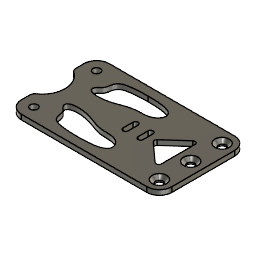
assembly frame (Autodesk Fusion 360 archive; units mm, degrees)
design "top plate"
part number: 2026-08-28-11-28-22-394
Autodesk Fusion 360 part; units mm, degrees
sketch "Sketch1" plane through (0, 0, 0) normal (0, 0, 1) x (1, 0, 0)
  line L0 (-30, 17.5) -> (30, 17.5)
  line L1 (30, 17.5) -> (30, -17.5)
  line L2 (30, -17.5) -> (-30, -17.5)
  line L3 (-30, -17.5) -> (-30, 17.5)
  dimension "d1" = 60
  dimension "d2" = 35
  dimension "d3" = 30
  dimension "d4" = 17.5
  constraint horizontal L0
  constraint vertical L1
  constraint horizontal L2
  constraint vertical L3
  measures "d1" distance of L1.end L2.end
  measures "d2" distance of L0 L2
  measures "d3" horizontal distance of origin L2.end
  measures "d4" vertical distance of origin L2.end
extrude "Extrude1" add sketch "Sketch1" along normal blind 2 contours L0 L1 L2 L3 picked at (-10, 5.833333)
sketch "Sketch2" plane through (0, 0, 2) normal (0, 0, 1) x (-1, 0, 0)
  line L0 (30, 17.5) -> (-30, 17.5)
  line L1 (-30, 17.5) -> (-30, -17.5)
  line L2 (-30, -17.5) -> (30, -17.5)
  line L3 (30, -17.5) -> (30, 17.5)
  point P0 (-25, -12.5)
  point P1 (-25, 0)
  point P2 (-25, 12.5)
  dimension "d7" = 25
  dimension "d8" = 12.5
  dimension "d9" = 5
  constraint vertical P0 P2
  constraint vertical P1 P2
  constraint horizontal origin P1
  measures "d7" distance of P0 P2
  measures "d8" distance of P1 P2
  measures "d9" distance of L1 P1
hole "Hole1" at (25, 12.5, 2) at (25, 0, 2) at (25, -12.5, 2) direction (0, 0, -1) diameter 3 end through all countersink diameter 5.76 countersink angle 90
sketch "Sketch3" plane through (0, 0, 2) normal (0, 0, 1) x (-1, 0, 0)
  circle A0 centre (-25, 0) radius 2.88
  circle A1 centre (-25, -12.5) radius 2.88
  circle A2 centre (-25, 12.5) radius 2.88
  line L0 (30, 17.5) -> (-30, 17.5)
  line L1 (-30, 17.5) -> (-30, -17.5)
  line L2 (-30, -17.5) -> (30, -17.5)
  line L3 (30, -17.5) -> (30, 17.5)
  point P0 (25, -12.5)
  point P1 (25, 12.5)
  dimension "d14" = 5
  constraint vertical P0 P1
  constraint horizontal A2.centre P1
  constraint horizontal A1.centre P0
  measures "d14" distance of L3 P0
hole "Hole2" at (-25, 12.5, 2) at (-25, -12.5, 2) direction (0, 0, -1) diameter 3 end through all
fillet "Fillet1" radius 5 4 edges at (-30, -17.5, 1) (-30, 17.5, 1) (30, -17.5, 1) (30, 17.5, 1)
sketch "Sketch4" plane through (0, 0, 2) normal (0, 0, 1) x (-1, 0, 0)
  circle A0 centre (25, -12.5) radius 1.5
  circle A1 centre (25, 12.5) radius 1.5
  circle A2 centre (-25, 0) radius 2.88
  circle A3 centre (-25, -12.5) radius 2.88
  circle A4 centre (-25, 12.5) radius 2.88
  arc A5 (-30, -12.5) -> (-25, -17.5) centre (-25, -12.5) ccw
  line L0 (-25, -17.5) -> (25, -17.5)
  arc A6 (25, -17.5) -> (30, -12.5) centre (25, -12.5) ccw
  line L1 (30, -12.5) -> (30, 12.5)
  arc A7 (30, 12.5) -> (25, 17.5) centre (25, 12.5) ccw
  line L2 (25, 17.5) -> (-25, 17.5)
  arc A8 (-25, 17.5) -> (-30, 12.5) centre (-25, 12.5) ccw
  line L3 (-30, 12.5) -> (-30, -12.5)
  line L4 (0, 2) -> (0, -2)
  arc A9 (-2, -2) -> (0, -2) centre (-1, -2) ccw
  line L5 (-2, -2) -> (-2, 2)
  arc A10 (0, 2) -> (-2, 2) centre (-1, 2) ccw
  line L6 (-8, -2) -> (-8, 2)
  arc A11 (-6, 2) -> (-8, 2) centre (-7, 2) ccw
  line L7 (-6, 2) -> (-6, -2)
  arc A12 (-8, -2) -> (-6, -2) centre (-7, -2) ccw
  dimension "d19" = 2
  dimension "d20" = 2
  dimension "d21" = 6
  dimension "d22" = 4
  dimension "d23" = 2
  dimension "d24" = 23
  constraint vertical L4
  constraint tangent L4 A9
  constraint tangent A9 L5
  constraint parallel L4 L5
  constraint tangent L5 A10
  constraint tangent L4 A10
  constraint vertical L7
  constraint tangent L7 A12
  constraint tangent L6 A12
  constraint parallel L6 L7
  constraint tangent L6 A11
  constraint tangent A11 L7
  constraint horizontal A10.centre A11.centre
  constraint horizontal A9.centre A12.centre
  measures "d19" distance of L4 L5
  measures "d20" distance of L6 L7
  measures "d21" distance of A10.centre A11.centre
  measures "d22" distance of A12.centre A11.centre
  measures "d23" vertical distance of origin A10.centre
  measures "d24" distance of L3 A11.centre
extrude "Extrude2" cut sketch "Sketch4" against normal blind 2 contours L4 A9 L5 A10 | L6 A11 L7 A12 picked at (-0.666667, -0.666667) picked at (-6.666667, -0.666667)
sketch "Sketch5" plane through (0, 0, 2) normal (0, 0, 1) x (-1, 0, 0)
  arc A0 (-30, -12.5) -> (-25, -17.5) centre (-25, -12.5) ccw
  line L0 (-25, -17.5) -> (25, -17.5)
  arc A1 (25, -17.5) -> (30, -12.5) centre (25, -12.5) ccw
  line L1 (30, -12.5) -> (30, 12.5)
  arc A2 (30, 12.5) -> (25, 17.5) centre (25, 12.5) ccw
  line L2 (25, 17.5) -> (-25, 17.5)
  arc A3 (-25, 17.5) -> (-30, 12.5) centre (-25, 12.5) ccw
  line L3 (-30, 12.5) -> (-30, -12.5)
  circle A4 centre (-25, 12.5) radius 2.88
  circle A5 centre (-25, -12.5) radius 2.88
  circle A6 centre (-25, 0) radius 2.88
  circle A7 centre (25, 12.5) radius 1.5
  circle A8 centre (25, -12.5) radius 1.5
  line L4 (-8, -2) -> (-8, 2)
  arc A9 (-6, 2) -> (-8, 2) centre (-7, 2) ccw
  line L5 (-6, 2) -> (-6, -2)
  arc A10 (-8, -2) -> (-6, -2) centre (-7, -2) ccw
  line L6 (0, 2) -> (0, -2)
  arc A11 (-2, -2) -> (0, -2) centre (-1, -2) ccw
  line L7 (-2, -2) -> (-2, 2)
  arc A12 (0, 2) -> (-2, 2) centre (-1, 2) ccw
  line L8 (-20, 9) -> (-10, 0)
  line L9 (-10, 0) -> (-20, -9)
  line L10 (-20, -9) -> (-20, 9)
  dimension "d27" = 18
  dimension "d28" = 9
  dimension "d29" = 2
  dimension "d30" = 5
  constraint vertical L10
  constraint horizontal A6.centre L8.end
  measures "d27" distance of L8.start L9.end
  measures "d28" vertical distance of L8.start L8.end
  measures "d29" distance of L4 L8.end
  measures "d30" distance of A6.centre L10
extrude "Extrude3" cut sketch "Sketch5" against normal blind 2 contours L8 L9 L10 picked at (-16.666667, 0)
fillet "Fillet2" radius 1 3 edges at (20, 9, 1) (10, 0, 1) (20, -9, 1)
sketch "Sketch6" plane through (0, 0, 2) normal (0, 0, 1) x (-1, 0, 0)
  line L0 (0, 2) -> (0, -2)
  arc A0 (-2, -2) -> (0, -2) centre (-1, -2) ccw
  line L1 (-2, -2) -> (-2, 2)
  arc A1 (0, 2) -> (-2, 2) centre (-1, 2) ccw
  line L2 (-8, -2) -> (-8, 2)
  arc A2 (-6, 2) -> (-8, 2) centre (-7, 2) ccw
  line L3 (-6, 2) -> (-6, -2)
  arc A3 (-8, -2) -> (-6, -2) centre (-7, -2) ccw
  circle A4 centre (25, -12.5) radius 1.5
  circle A5 centre (25, 12.5) radius 1.5
  circle A6 centre (-25, 0) radius 2.88
  circle A7 centre (-25, -12.5) radius 2.88
  circle A8 centre (-25, 12.5) radius 2.88
  arc A9 (-30, -12.5) -> (-25, -17.5) centre (-25, -12.5) ccw
  line L4 (-25, -17.5) -> (25, -17.5)
  arc A10 (25, -17.5) -> (30, -12.5) centre (25, -12.5) ccw
  line L5 (30, -12.5) -> (30, 12.5)
  arc A11 (30, 12.5) -> (25, 17.5) centre (25, 12.5) ccw
  line L6 (25, 17.5) -> (-25, 17.5)
  arc A12 (-25, 17.5) -> (-30, 12.5) centre (-25, 12.5) ccw
  line L7 (-30, 12.5) -> (-30, -12.5)
  line L8 (-18.331035, 7.497932) -> (-10.825882, 0.743294)
  arc A13 (-10.825882, -0.743294) -> (-10.825882, 0.743294) centre (-11.494847, 0) ccw
  line L9 (-10.825882, -0.743294) -> (-18.331035, -7.497932)
  arc A14 (-20, -6.754638) -> (-18.331035, -7.497932) centre (-19, -6.754638) ccw
  line L10 (-20, -6.754638) -> (-20, 6.754638)
  arc A15 (-18.331035, 7.497932) -> (-20, 6.754638) centre (-19, 6.754638) ccw
  spline S0 degree 5 poles (18.380032, 7.470408) (18.508831, 7.354913) (18.77546, 7.128382) (19.181173, 6.784257) (19.624796, 6.24706) (19.853273, 5.512207) (19.639438, 4.826201) (18.966235, 4.297472) (17.899583, 3.963879) (16.558455, 3.828061) (15.084144, 3.862596) (13.611643, 4.027068) (12.236621, 4.281257) (10.995215, 4.59591) (9.883195, 4.947788) (8.86805, 5.317825) (7.904124, 5.687831) (6.94558, 6.038335) (5.962404, 6.344609) (4.940277, 6.582654) (3.876158, 6.737723) (2.77522, 6.81234) (1.647499, 6.833834) (0.504023, 6.864122) (-0.638288, 6.982513) (-1.751039, 7.266083) (-2.788313, 7.769913) (-3.682341, 8.509644) (-4.334343, 9.43699) (-4.63343, 10.45589) (-4.4867, 11.45368) (-3.842937, 12.325344) (-2.725459, 13.005044) (-1.23989, 13.479891) (0.46534, 13.77111) (2.228719, 13.922102) (3.908228, 13.984114) (5.415003, 14.002308) (6.741154, 14.003243) (8.00784, 13.976751) (9.272387, 13.922197) (10.560388, 13.837678) (11.862231, 13.718377) (13.142468, 13.550878) (14.344661, 13.310565) (15.39556, 12.954121) (16.223805, 12.433521) (16.787322, 11.719936) (17.095905, 10.823716) (17.240718, 9.818126) (17.404226, 8.852016) (17.678232, 8.205604) (18.002665, 7.821352) (18.251232, 7.585904) (18.380032, 7.470408) knots 0 0 0 0 0 0 0.02 0.04 0.06 0.08 0.1 0.12 0.14 0.16 0.18 0.2 0.22 0.24 0.26 0.28 0.3 0.32 0.34 0.36 0.38 0.4 0.42 0.44 0.46 0.48 0.5 0.52 0.54 0.56 0.58 0.6 0.62 0.64 0.66 0.68 0.7 0.72 0.74 0.76 0.78 0.8 0.82 0.84 0.86 0.88 0.9 0.92 0.94 0.96 0.98 1 1 1 1 1 1
  line L11 (3, 14) -> (9, 14)
  line L12 (-1.75, 0) -> (-22.5, 0)
  spline S1 degree 5 poles (18.380032, -7.470408) (18.508831, -7.354913) (18.77546, -7.128382) (19.181173, -6.784257) (19.624796, -6.24706) (19.853273, -5.512207) (19.639438, -4.826201) (18.966235, -4.297472) (17.899583, -3.963879) (16.558455, -3.828061) (15.084144, -3.862596) (13.611643, -4.027068) (12.236621, -4.281257) (10.995215, -4.59591) (9.883195, -4.947788) (8.86805, -5.317825) (7.904124, -5.687831) (6.94558, -6.038335) (5.962404, -6.344609) (4.940277, -6.582654) (3.876158, -6.737723) (2.77522, -6.81234) (1.647499, -6.833834) (0.504023, -6.864122) (-0.638288, -6.982513) (-1.751039, -7.266083) (-2.788313, -7.769913) (-3.682341, -8.509644) (-4.334343, -9.43699) (-4.63343, -10.45589) (-4.4867, -11.45368) (-3.842937, -12.325344) (-2.725459, -13.005044) (-1.23989, -13.479891) (0.46534, -13.77111) (2.228719, -13.922102) (3.908228, -13.984114) (5.415003, -14.002308) (6.741154, -14.003243) (8.00784, -13.976751) (9.272387, -13.922197) (10.560388, -13.837678) (11.862231, -13.718377) (13.142468, -13.550878) (14.344661, -13.310565) (15.39556, -12.954121) (16.223805, -12.433521) (16.787322, -11.719936) (17.095905, -10.823716) (17.240718, -9.818126) (17.404226, -8.852016) (17.678232, -8.205604) (18.002665, -7.821352) (18.251232, -7.585904) (18.380032, -7.470408) knots 0 0 0 0 0 0 0.02 0.04 0.06 0.08 0.1 0.12 0.14 0.16 0.18 0.2 0.22 0.24 0.26 0.28 0.3 0.32 0.34 0.36 0.38 0.4 0.42 0.44 0.46 0.48 0.5 0.52 0.54 0.56 0.58 0.6 0.62 0.64 0.66 0.68 0.7 0.72 0.74 0.76 0.78 0.8 0.82 0.84 0.86 0.88 0.9 0.92 0.94 0.96 0.98 1 1 1 1 1 1
  line L13 (15.765908, 9.814509) -> (20.994155, 5.126308)
  line L14 (15.765908, -9.814509) -> (20.994155, -5.126308)
  line L15 (3, -14) -> (9, -14)
  line L16 (3, -14) -> (9, -14)
  point P0 (19.670054, 5.126308)
  point P1 (14, 4)
  point P2 (7.685327, 5.764249)
  point P3 (2.650077, 6.80459)
  point P4 (-3, 8)
  point P5 (-4, 12)
  point P6 (6, 14)
  point P7 (13.511236, 13.462772)
  point P8 (17, 11)
  point P9 (-3, -8)
  point P10 (17, -11)
  point P11 (-4, -12)
  point P12 (19.670054, -5.126308)
  point P13 (2.650077, -6.80459)
  point P14 (13.511236, -13.462772)
  point P15 (7.685327, -5.764249)
  point P16 (14, -4)
  point P17 (6, -14)
  constraint midpoint P6 L11
  constraint symmetric P1 L12 P16
  constraint symmetric P4 L12 P9
  constraint symmetric P5 L12 P11
  constraint symmetric P6 L12 P17
  constraint symmetric P8 L12 P10
  constraint symmetric L11.start L12 L15.start
  constraint symmetric L11.end L12 L15.end
extrude "Extrude4" cut sketch "Sketch6" against normal blind 2 contours S0 L13 | S0 L13 | S1 L14 | S1 L14 picked at (8.380911, 11.233696) picked at (18.784558, 7.110333) picked at (18.784558, -7.110333) picked at (8.380911, -11.233696)
sketch "Sketch7" plane through (0, 0, 2) normal (0, 0, 1) x (-1, 0, 0)
  line L0 (-18.331035, 7.497932) -> (-10.825882, 0.743294)
  arc A0 (-10.825882, -0.743294) -> (-10.825882, 0.743294) centre (-11.494847, 0) ccw
  line L1 (-10.825882, -0.743294) -> (-18.331035, -7.497932)
  arc A1 (-20, -6.754638) -> (-18.331035, -7.497932) centre (-19, -6.754638) ccw
  line L2 (-20, -6.754638) -> (-20, 6.754638)
  arc A2 (-18.331035, 7.497932) -> (-20, 6.754638) centre (-19, 6.754638) ccw
  arc A3 (-30, -12.5) -> (-25, -17.5) centre (-25, -12.5) ccw
  line L3 (-25, -17.5) -> (25, -17.5)
  arc A4 (25, -17.5) -> (30, -12.5) centre (25, -12.5) ccw
  line L4 (30, -12.5) -> (30, 12.5)
  arc A5 (30, 12.5) -> (25, 17.5) centre (25, 12.5) ccw
  line L5 (25, 17.5) -> (-25, 17.5)
  arc A6 (-25, 17.5) -> (-30, 12.5) centre (-25, 12.5) ccw
  line L6 (-30, 12.5) -> (-30, -12.5)
  circle A7 centre (-25, 12.5) radius 2.88
  circle A8 centre (-25, -12.5) radius 2.88
  circle A9 centre (-25, 0) radius 2.88
  circle A10 centre (25, 12.5) radius 1.5
  circle A11 centre (25, -12.5) radius 1.5
  line L7 (-8, -2) -> (-8, 2)
  arc A12 (-6, 2) -> (-8, 2) centre (-7, 2) ccw
  line L8 (-6, 2) -> (-6, -2)
  arc A13 (-8, -2) -> (-6, -2) centre (-7, -2) ccw
  line L9 (0, 2) -> (0, -2)
  arc A14 (-2, -2) -> (0, -2) centre (-1, -2) ccw
  line L10 (-2, -2) -> (-2, 2)
  arc A15 (0, 2) -> (-2, 2) centre (-1, 2) ccw
  spline S0 degree 5 poles (18.380032, 7.470408) (18.508831, 7.354913) (18.77546, 7.128382) (19.181173, 6.784257) (19.624796, 6.24706) (19.853273, 5.512207) (19.639438, 4.826201) (18.966235, 4.297472) (17.899583, 3.963879) (16.558455, 3.828061) (15.084144, 3.862596) (13.611643, 4.027068) (12.236621, 4.281257) (10.995215, 4.59591) (9.883195, 4.947788) (8.86805, 5.317825) (7.904124, 5.687831) (6.94558, 6.038335) (5.962404, 6.344609) (4.940277, 6.582654) (3.876158, 6.737723) (2.77522, 6.81234) (1.647499, 6.833834) (0.504023, 6.864122) (-0.638288, 6.982513) (-1.751039, 7.266083) (-2.788313, 7.769913) (-3.682341, 8.509644) (-4.334343, 9.43699) (-4.63343, 10.45589) (-4.4867, 11.45368) (-3.842937, 12.325344) (-2.725459, 13.005044) (-1.23989, 13.479891) (0.46534, 13.77111) (2.228719, 13.922102) (3.908228, 13.984114) (5.415003, 14.002308) (6.741154, 14.003243) (8.00784, 13.976751) (9.272387, 13.922197) (10.560388, 13.837678) (11.862231, 13.718377) (13.142468, 13.550878) (14.344661, 13.310565) (15.39556, 12.954121) (16.223805, 12.433521) (16.787322, 11.719936) (17.095905, 10.823716) (17.240718, 9.818126) (17.404226, 8.852016) (17.678232, 8.205604) (18.002665, 7.821352) (18.251232, 7.585904) (18.380032, 7.470408) knots 0 0 0 0 0 0 0.02 0.04 0.06 0.08 0.1 0.12 0.14 0.16 0.18 0.2 0.22 0.24 0.26 0.28 0.3 0.32 0.34 0.36 0.38 0.4 0.42 0.44 0.46 0.48 0.5 0.52 0.54 0.56 0.58 0.6 0.62 0.64 0.66 0.68 0.7 0.72 0.74 0.76 0.78 0.8 0.82 0.84 0.86 0.88 0.9 0.92 0.94 0.96 0.98 1 1 1 1 1 1
  spline S1 degree 5 poles (6, -14) (5.876992, -14) (5.47862, -13.999252) (4.781623, -13.994037) (3.724622, -13.977335) (2.228719, -13.922102) (0.46534, -13.77111) (-1.23989, -13.479891) (-2.725459, -13.005044) (-3.842937, -12.325344) (-4.4867, -11.45368) (-4.63343, -10.45589) (-4.334343, -9.43699) (-3.682341, -8.509644) (-2.788313, -7.769913) (-1.751039, -7.266083) (-0.638288, -6.982513) (0.504023, -6.864122) (1.647499, -6.833834) (2.77522, -6.81234) (3.876158, -6.737723) (4.940277, -6.582654) (5.962404, -6.344609) (6.94558, -6.038335) (7.904124, -5.687831) (8.86805, -5.317825) (9.883195, -4.947788) (10.995215, -4.59591) (12.236621, -4.281257) (13.611643, -4.027068) (15.084144, -3.862596) (16.558455, -3.828061) (17.899583, -3.963879) (18.966235, -4.297472) (19.639438, -4.826201) (19.853273, -5.512207) (19.624796, -6.24706) (19.181173, -6.784257) (18.77546, -7.128382) (18.508831, -7.354913) (18.380032, -7.470408) (18.251232, -7.585904) (18.002665, -7.821352) (17.678232, -8.205604) (17.404226, -8.852016) (17.240718, -9.818126) (17.095905, -10.823716) (16.787322, -11.719936) (16.223805, -12.433521) (15.39556, -12.954121) (14.344661, -13.310565) (13.142468, -13.550878) (11.862231, -13.718377) (10.560388, -13.837678) (9.272387, -13.922197) (8.122508, -13.971804) (7.224193, -13.992851) (6.562693, -13.99904) (6.148297, -14) (6, -14) knots -0.70906788 -0.70906788 -0.70906788 -0.70906788 -0.70906788 -0.70906788 -0.7 -0.68 -0.66 -0.64 -0.62 -0.6 -0.58 -0.56 -0.54 -0.52 -0.5 -0.48 -0.46 -0.44 -0.42 -0.4 -0.38 -0.36 -0.34 -0.32 -0.3 -0.28 -0.26 -0.24 -0.22 -0.2 -0.18 -0.16 -0.14 -0.12 -0.1 -0.08 -0.06 -0.04 -0.02 0 0 0 0 0 0.02 0.04 0.06 0.08 0.1 0.12 0.14 0.16 0.18 0.2 0.22 0.24 0.26 0.28 0.29093212 0.29093212 0.29093212 0.29093212 0.29093212 0.29093212
  arc A16 (30, 8) -> (30, -8) centre (34.123106, 0) ccw
  line L11 (30, -12.5) -> (30, 12.5)
  dimension "d37" = 16
  dimension "d38" = 4.5
  dimension "d39" = 9
  constraint coincident L4 A16.start
  constraint coincident L4 A16.end
  measures "d37" distance of A16.end A16.start
  measures "d38" vertical distance of A5.centre A16.start
  measures "d39" radius of A16
extrude "Extrude5" cut sketch "Sketch7" against normal blind 4 contours L4 A16 L11 picked at (27.197455, 1.677028)
fillet "Fillet3" radius 2 2 edges at (-30, 8, 1) (-30, -8, 1)
equation "d8 = ( 25 / 2 ) * 1 mm"
equation "d38 = ( ( 25 - 16 ) / 2 ) * 1 mm"

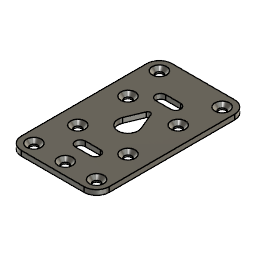
design "bottom plate"
part number: 2026-08-28-11-00-39-377
Autodesk Fusion 360 part; units mm, degrees
sketch "Sketch2" plane through (0, 0, 0) normal (0, 0, 1) x (1, 0, 0)
  line L0 (0, 0) -> (35, 0)
  line L1 (35, 0) -> (35, 60)
  line L2 (35, 60) -> (0, 60)
  line L3 (0, 60) -> (0, 0)
  dimension "d1" = 35
  dimension "d2" = 60
  constraint horizontal L0
  constraint vertical L1
  constraint horizontal L2
  constraint vertical L3
  constraint coincident L0.start L3.end
  measures "d1" distance of L0.start L0.end
  measures "d2" distance of L0.end L1.end
extrude "Extrude1" add sketch "Sketch2" along normal blind 2
sketch "Sketch3" plane through (0, 0, 2) normal (0, 0, 1) x (-1, 0, 0)
  line L0 (0, -60) -> (0, 0)
  line L1 (0, 0) -> (-35, 0)
  line L2 (-35, 0) -> (-35, -60)
  line L3 (-35, -60) -> (0, -60)
  point P0 (-5, -5)
  point P1 (-17.5, -5)
  point P2 (-30, -5)
  point P3 (-5, -55)
  point P4 (-30, -55)
  point P5 (-7.5, -40)
  point P6 (-27.5, -40)
  point P7 (-7.5, -20)
  point P8 (-27.5, -20)
  dimension "d5" = 25
  dimension "d6" = 12.5
  dimension "d7" = 25
  dimension "d8" = 5
  dimension "d9" = 5
  dimension "d10" = 5
  dimension "d11" = 5
  dimension "d12" = 20
  dimension "d13" = 20
  dimension "d14" = 20
  dimension "d15" = 7.5
  constraint vertical P5 P7
  constraint vertical P6 P8
  constraint horizontal P7 P8
  constraint horizontal P5 P6
  constraint horizontal P3 P4
  constraint horizontal P0 P1
  constraint horizontal P1 P2
  measures "d5" distance of P0 P2
  measures "d6" distance of P0 P1
  measures "d7" distance of P3 P4
  measures "d8" distance of L0 P3
  measures "d9" distance of L3 P3
  measures "d10" distance of L1 P0
  measures "d11" distance of L0 P0
  measures "d12" distance of P7 P8
  measures "d13" distance of P6 P8
  measures "d14" distance of L1 P8
  measures "d15" distance of L2 P8
hole "Hole1" at (5, 5, 2) at (7.5, 20, 2) at (7.5, 40, 2) at (5, 55, 2) at (30, 55, 2) at (27.5, 40, 2) at (27.5, 20, 2) at (17.5, 5, 2) at (30, 5, 2) direction (0, 0, -1) diameter 3 end through all countersink diameter 5.76 countersink angle 90
fillet "Fillet1" radius 5 4 edges at (0, 0, 1) (35, 0, 1) (35, 60, 1) (0, 60, 1)
sketch "Sketch4" plane through (0, 0, 2) normal (0, 0, 1) x (-1, 0, 0)
  arc A0 (-5, -60) -> (0, -55) centre (-5, -55) ccw
  line L0 (0, -55) -> (0, -5)
  arc A1 (0, -5) -> (-5, 0) centre (-5, -5) ccw
  line L1 (-5, 0) -> (-30, 0)
  arc A2 (-30, 0) -> (-35, -5) centre (-30, -5) ccw
  line L2 (-35, -5) -> (-35, -55)
  arc A3 (-35, -55) -> (-30, -60) centre (-30, -55) ccw
  line L3 (-30, -60) -> (-5, -60)
  circle A4 centre (-30, -5) radius 2.88
  circle A5 centre (-27.5, -20) radius 2.88
  circle A6 centre (-30, -55) radius 2.88
  circle A7 centre (-7.5, -40) radius 2.88
  circle A8 centre (-5, -5) radius 2.88
  circle A9 centre (-7.5, -20) radius 2.88
  circle A10 centre (-5, -55) radius 2.88
  circle A11 centre (-27.5, -40) radius 2.88
  circle A12 centre (-17.5, -5) radius 2.88
  arc A13 (-20.5, -12) -> (-20.5, -16) centre (-20.5, -14) ccw
  arc A14 (-20.5, -44) -> (-20.5, -48) centre (-20.5, -46) ccw
  arc A15 (-14.5, -48) -> (-14.5, -44) centre (-14.5, -46) ccw
  arc A16 (-13.8045, -31.5307) -> (-21.1955, -31.5307) centre (-17.5, -30) ccw
  line L4 (-14.5, -16) -> (-20.5, -16)
  line L5 (-18.4241, -38.2214) -> (-21.1955, -31.5307)
  line L6 (-20.5, -12) -> (-14.5, -12)
  line L7 (-13.8045, -31.5307) -> (-16.576, -38.2218)
  arc A17 (-18.4241, -38.2214) -> (-16.576, -38.2218) centre (-17.5, -37.8394) ccw
  line L8 (-14.5, -48) -> (-20.5, -48)
  line L9 (-20.5, -44) -> (-14.5, -44)
  arc A18 (-14.5, -16) -> (-14.5, -12) centre (-14.5, -14) ccw
  dimension "d22" = 16
  dimension "d24" = 7.8394
  dimension "d25" = 3
  dimension "d26" = 3
  dimension "d27" = 6
  dimension "d28" = 6
  dimension "d29" = 4
  dimension "d30" = 4
  dimension "d31" = 16
  dimension "d32" = 30
  dimension "d33" = 17.5
  constraint vertical A16.centre A17.centre
  constraint horizontal A15.centre A14.centre
  constraint horizontal A13.centre A18.centre
  measures "d22" vertical distance of A16.centre A18.centre
  measures "d24" distance of A16.centre A17.centre
  measures "d25" horizontal distance of A17.centre A15.centre
  measures "d26" horizontal distance of A16.centre A18.centre
  measures "d27" distance of A13.centre A18.centre
  measures "d28" distance of A15.centre A14.centre
  measures "d29" distance of L8 L9
  measures "d30" distance of L4 L6
  measures "d31" vertical distance of A16.centre A15.centre
  measures "d32" distance of L3 A16.centre
  measures "d33" distance of L0 A16.centre
extrude "Extrude2" cut sketch "Sketch4" against normal blind 3 contours A13 L4 L6 A18 | A14 A15 L8 L9 | A16 L5 L7 A17
equation "d6 = ( 25 / 2 ) * 1 mm"
equation "d15 = ( ( 35 - 20 ) / 2 ) * 1 mm"

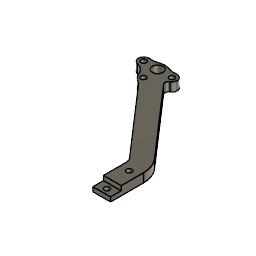
design "arm"
part number: 2026-08-28-11-39-51-718
Autodesk Fusion 360 part; units mm, degrees
sketch "Sketch1" plane through (0, 0, 0) normal (0, 0, 1) x (1, 0, 0)
  line L0 (-5, -3) -> (-5, 17.5)
  line L1 (-5, 17.5) -> (-48.0297, 67)
  line L2 (-48.0297, 67) -> (-34.7796, 67)
  line L3 (-34.7796, 67) -> (5, 21.2388)
  line L4 (5, 21.2388) -> (5, -3)
  line L5 (5, -3) -> (-5, -3)
  dimension "d1" = 10
  dimension "d2" = 5
  dimension "d3" = 10
  dimension "d4" = 20.5
  dimension "d5" = 139
  dimension "d6" = 3
  dimension "d7" = 67
  constraint vertical L0
  constraint perpendicular L0 L2
  constraint perpendicular L2 L4
  constraint perpendicular L0 L5
  constraint parallel L1 L3
  measures "d1" distance of L0 L4
  measures "d2" horizontal distance of origin L0.start
  measures "d3" distance of L1 L3
  measures "d4" distance of L0.start L0.end
  measures "d5" angle of L0 L1
  measures "d6" distance of origin L5
  measures "d7" vertical distance of origin L1.end
extrude "Extrude1" add sketch "Sketch1" along normal blind 5
sketch "Sketch2" plane through (0, 0, 5) normal (0, 0, 1) x (-1, 0, 0)
  line L0 (-5, 3) -> (-5, -21.2388)
  line L1 (-5, -21.2388) -> (34.7796, -67)
  line L2 (34.7796, -67) -> (48.0297, -67)
  line L3 (48.0297, -67) -> (5, -17.5)
  line L4 (5, -17.5) -> (5, 3)
  line L5 (5, 3) -> (-5, 3)
  line L6 (5, 3) -> (-5, 3)
  line L7 (-5, 3) -> (-5, -3)
  line L8 (-5, -3) -> (5, -3)
  line L9 (5, -3) -> (5, 3)
  dimension "d10" = 6
  constraint horizontal L6
  constraint vertical L7
  constraint horizontal L8
  constraint vertical L9
  constraint coincident L0 L7.end
  constraint coincident L4.end L5.start
  measures "d10" distance of L6 L8
extrude "Extrude2" cut sketch "Sketch2" against normal blind 2.5 contours L0 L4 L5 L6 L7 L8 L9
sketch "Sketch3" plane through (0, 0, 5) normal (0, 0, 1) x (-1, 0, 0)
  line L0 (5, -3) -> (-5, -3)
  line L1 (-5, -3) -> (-5, -21.2388)
  line L2 (-5, -21.2388) -> (34.7796, -67)
  line L3 (34.7796, -67) -> (48.0297, -67)
  line L4 (48.0297, -67) -> (5, -17.5)
  line L5 (5, -17.5) -> (5, -3)
  circle A0 centre (0, 0) radius 1.5
  circle A1 centre (0, -12.5) radius 1.5
  dimension "d13" = 3
  dimension "d14" = 3
  dimension "d15" = 12.5
  constraint coincident A0.centre origin
  constraint vertical A0.centre A1.centre
  measures "d13" diameter of A0
  measures "d14" diameter of A1
  measures "d15" distance of A0.centre A1.centre
extrude "Extrude3" cut sketch "Sketch3" against normal through all contours A0 | A1
sketch "Sketch4" plane through (0, 0, 5) normal (0, 0, 1) x (-1, 0, 0)
  circle A0 centre (0, -12.5) radius 1.5
  line L0 (5, -3) -> (-5, -3)
  line L1 (-5, -3) -> (-5, -21.2388)
  line L2 (-5, -21.2388) -> (34.7796, -67)
  line L3 (34.7796, -67) -> (48.0297, -67)
  line L4 (48.0297, -67) -> (5, -17.5)
  line L5 (5, -17.5) -> (5, -3)
  line L6 (48.0297, -67) -> (49.4046, -67)
  arc A1 (49.4046, -73) -> (49.4046, -67) centre (49.4046, -70) ccw
  line L7 (49.4046, -73) -> (33.4046, -73)
  arc A2 (33.4046, -67) -> (33.4046, -73) centre (33.4046, -70) ccw
  line L8 (33.4046, -67) -> (34.7796, -67)
  dimension "d17" = 6
  dimension "d18" = 16
  constraint coincident L3.end L4.start
  constraint parallel L3 L6
  constraint tangent L6 A1
  constraint parallel L6 L7
  constraint tangent L7 A2
  constraint coincident L2.end L3.start
  constraint parallel L3 L8
  constraint vertical L6.end A1.start
  constraint vertical L7.end A2.start
  constraint equal L6 L8
  measures "d17" distance of L7 L8
  measures "d18" distance of A1.centre A2.centre
extrude "Extrude4" add sketch "Sketch4" against normal blind 5 contours L3 L6 A1 L7 A2 L8
hole "Hole1" at (-49.4046, 70, 5) at (-33.4046, 70, 5) direction (0, 0, -1) diameter 3 end through all
sketch "Sketch5" plane through (0, 0, 5) normal (0, 0, 1) x (-1, 0, 0)
  circle A0 centre (49.4046, -70) radius 1.5
  circle A1 centre (33.4046, -70) radius 1.5
  circle A2 centre (0, -12.5) radius 1.5
  line L0 (5, -3) -> (-5, -3)
  line L1 (-5, -3) -> (-5, -21.2388)
  line L2 (-5, -21.2388) -> (34.7796, -67)
  line L3 (34.7796, -67) -> (33.4046, -67)
  arc A3 (33.4046, -67) -> (33.4046, -73) centre (33.4046, -70) ccw
  line L4 (33.4046, -73) -> (49.4046, -73)
  arc A4 (49.4046, -73) -> (49.4046, -67) centre (49.4046, -70) ccw
  line L5 (49.4046, -67) -> (48.0297, -67)
  line L6 (48.0297, -67) -> (5, -17.5)
  line L7 (5, -17.5) -> (5, -3)
  circle A5 centre (41.4046, -62) radius 1.5
  dimension "d23" = 3
  dimension "d24" = 8
  dimension "d25" = 8
  measures "d23" diameter of A5
  measures "d24" horizontal distance of A0.centre A5.centre
  measures "d25" vertical distance of A1.centre A5.centre
extrude "Extrude5" cut sketch "Sketch5" against normal blind 6 contours A5
sketch "Sketch6" plane through (0, 0, 5) normal (0, 0, 1) x (-1, 0, 0)
  circle A0 centre (41.4046, -62) radius 1.5
  circle A1 centre (49.4046, -70) radius 1.5
  circle A2 centre (33.4046, -70) radius 1.5
  circle A3 centre (0, -12.5) radius 1.5
  line L0 (5, -3) -> (-5, -3)
  line L1 (-5, -3) -> (-5, -21.2388)
  line L2 (-5, -21.2388) -> (34.7796, -67)
  line L3 (34.7796, -67) -> (33.4046, -67)
  arc A4 (33.4046, -67) -> (33.4046, -73) centre (33.4046, -70) ccw
  line L4 (33.4046, -73) -> (49.4046, -73)
  arc A5 (49.4046, -73) -> (49.4046, -67) centre (49.4046, -70) ccw
  line L5 (49.4046, -67) -> (48.0297, -67)
  line L6 (48.0297, -67) -> (5, -17.5)
  line L7 (5, -17.5) -> (5, -3)
  arc A6 (44.9987, -63.5133) -> (40.4063, -58.2303) centre (37.2733, -65.5913) ccw
  line L8 (41.4046, -62) -> (35.9177, -66.7697)
  dimension "d28" = 7
  dimension "d29" = 8
  constraint coincident L6 A6.end
  constraint coincident L6 A6.start
  constraint coincident A0.centre L8.start
  constraint perpendicular L2 L8
  constraint coincident A6.centre L8
  measures "d28" distance of A6.start A6.end
  measures "d29" radius of A6
extrude "Extrude6" add sketch "Sketch6" against normal blind 5 contours L6 A6
sketch "Sketch7" plane through (0, 0, 5) normal (0, 0, 1) x (-1, 0, 0)
  circle A0 centre (41.4046, -62) radius 1.5
  circle A1 centre (49.4046, -70) radius 1.5
  circle A2 centre (33.4046, -70) radius 1.5
  circle A3 centre (0, -12.5) radius 1.5
  line L0 (5, -3) -> (-5, -3)
  line L1 (-5, -3) -> (-5, -21.2388)
  line L2 (-5, -21.2388) -> (34.7796, -67)
  line L3 (34.7796, -67) -> (33.4046, -67)
  arc A4 (33.4046, -67) -> (33.4046, -73) centre (33.4046, -70) ccw
  line L4 (33.4046, -73) -> (49.4046, -73)
  arc A5 (49.4046, -73) -> (49.4046, -67) centre (49.4046, -70) ccw
  line L5 (49.4046, -67) -> (48.0297, -67)
  line L6 (48.0297, -67) -> (44.9987, -63.5133)
  arc A6 (44.9987, -63.5133) -> (40.4063, -58.2303) centre (37.2733, -65.5913) ccw
  line L7 (40.4063, -58.2303) -> (5, -17.5)
  line L8 (5, -17.5) -> (5, -3)
  circle A7 centre (41.4046, -70) radius 3
  dimension "d32" = 6
  constraint horizontal A1.centre A7.centre
  constraint vertical A0.centre A7.centre
  measures "d32" diameter of A7
extrude "Extrude7" cut sketch "Sketch7" against normal blind 5.5 contours A7
sketch "Sketch8" plane through (0, 0, 5) normal (0, 0, 1) x (-1, 0, 0)
  line L0 (5, -3) -> (-5, -3)
  line L1 (-5, -3) -> (-5, -21.2388)
  line L2 (-5, -21.2388) -> (34.7796, -67)
  line L3 (34.7796, -67) -> (33.4046, -67)
  arc A0 (33.4046, -67) -> (33.4046, -73) centre (33.4046, -70) ccw
  line L4 (33.4046, -73) -> (41.4046, -73)
  circle A1 centre (41.4046, -70) radius 3
  line L5 (41.4046, -73) -> (49.4046, -73)
  arc A2 (49.4046, -73) -> (49.4046, -67) centre (49.4046, -70) ccw
  line L6 (49.4046, -67) -> (48.0297, -67)
  line L7 (48.0297, -67) -> (44.9987, -63.5133)
  arc A3 (44.9987, -63.5133) -> (40.4063, -58.2303) centre (37.2733, -65.5913) ccw
  line L8 (40.4063, -58.2303) -> (5, -17.5)
  line L9 (5, -17.5) -> (5, -3)
  circle A4 centre (0, -12.5) radius 1.5
  circle A5 centre (33.4046, -70) radius 1.5
  circle A6 centre (49.4046, -70) radius 1.5
  circle A7 centre (41.4046, -62) radius 1.5
  arc A8 (37.4046, -73) -> (45.4046, -73) centre (41.4046, -66.0718) ccw
  dimension "d35" = 8
  dimension "d36" = 4
  dimension "d37" = 8
  constraint coincident L4 A8.start
  constraint coincident L5 A8.end
  measures "d35" distance of A8.end A8.start
  measures "d36" horizontal distance of A1.centre A8.end
  measures "d37" radius of A8
extrude "Extrude8" add sketch "Sketch8" against normal blind 5 contours L4 L5 A8
fillet "Fillet1" radius 7 1 edges at (-48.0297, 67, 2.5)
fillet "Fillet2" radius 10 2 edges at (-45.4046, 73, 2.5) (-37.4046, 73, 2.5)
fillet "Fillet3" radius 2 1 edges at (-34.7796, 67, 2.5)
fillet "Fillet4" radius 5 2 edges at (-44.9987, 63.5133, 2.5) (-40.4063, 58.2303, 2.5)
fillet "Fillet5" radius 5 1 edges at (-5, 17.5, 2.5)
fillet "Fillet6" radius 15 1 edges at (5, 21.2388, 2.5)
equation "d4 = ( 35 / 2 ) * 1 mm + 3 mm"
equation "d15 = ( 25 / 2 ) * 1 mm"

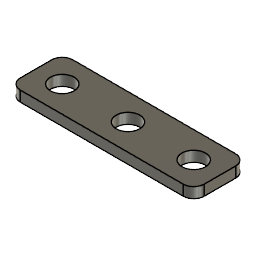
design "compression"
part number: 2026-08-28-11-17-18-521
Autodesk Fusion 360 part; units mm, degrees
sketch "Sketch1" plane through (0, 0, 0) normal (0, 0, 1) x (1, 0, 0)
  line L0 (-17.5, 5) -> (17.5, 5)
  line L1 (17.5, 5) -> (17.5, -5)
  line L2 (17.5, -5) -> (-17.5, -5)
  line L3 (-17.5, -5) -> (-17.5, 5)
  dimension "d1" = 10
  dimension "d2" = 35
  dimension "d3" = 17.5
  dimension "d4" = 5
  constraint horizontal L0
  constraint vertical L1
  constraint horizontal L2
  constraint vertical L3
  measures "d1" distance of L0 L2
  measures "d2" distance of L1 L3
  measures "d3" horizontal distance of origin L1.end
  measures "d4" vertical distance of origin L1.end
extrude "Extrude1" add sketch "Sketch1" along normal blind 2
sketch "Sketch2" plane through (0, 0, 2) normal (0, 0, 1) x (-1, 0, 0)
  line L0 (17.5, 5) -> (-17.5, 5)
  line L1 (-17.5, 5) -> (-17.5, -5)
  line L2 (-17.5, -5) -> (17.5, -5)
  line L3 (17.5, -5) -> (17.5, 5)
  point P0 (12.5, 0)
  point P1 (-12.5, 0)
  dimension "d7" = 12.5
  dimension "d8" = 12.5
  constraint horizontal origin P1
  constraint horizontal origin P0
  measures "d7" distance of origin P0
  measures "d8" distance of origin P1
hole "Hole1" at (-12.5, 0, 2) at (0, 0, 2) at (12.5, 0, 2) direction (0, 0, -1) diameter 4.5 end through all
fillet "Fillet1" radius 2 4 edges at (-17.5, -5, 1) (17.5, -5, 1) (17.5, 5, 1) (-17.5, 5, 1)

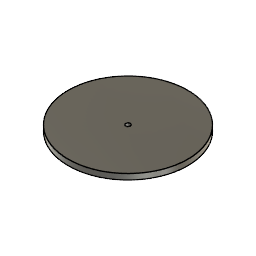
design "prop"
part number: 2026-08-29-09-26-35-726
Autodesk Fusion 360 part; units mm, degrees
sketch "Sketch1" plane through (0, 0, 0) normal (0, 0, 1) x (1, 0, 0)
  circle A0 centre (0, 0) radius 65.15
  dimension "d1" = 130.3
  constraint coincident A0.centre origin
  measures "d1" diameter of A0
extrude "Extrude1" add sketch "Sketch1" along normal blind 6.2
sketch "Sketch2" plane through (0, 0, 6.2) normal (0, 0, 1) x (-1, 0, 0)
  circle A0 centre (0, 0) radius 65.15
  circle A1 centre (0, 0) radius 2.5
  dimension "d4" = 5
  constraint concentric A0 A1
  measures "d4" diameter of A1
extrude "Extrude2" cut sketch "Sketch2" against normal blind 11 contours A1

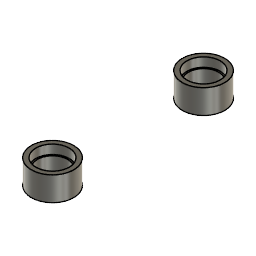
design "antenna mount"
part number: 2026-08-29-16-15-58-114
Autodesk Fusion 360 part; units mm, degrees
sketch "Sketch1" plane through (0, 0, 0) normal (0, 0, 1) x (1, 0, 0)
  circle A0 centre (0, 12.5) radius 3.5
  circle A1 centre (0, -12.5) radius 3.5
  dimension "d1" = 7
  dimension "d2" = 7
  dimension "d3" = 25
  dimension "d4" = 12.5
  constraint vertical origin A1.centre
  constraint vertical origin A0.centre
  measures "d1" diameter of A1
  measures "d2" diameter of A0
  measures "d3" distance of A0.centre A1.centre
  measures "d4" distance of origin A1.centre
extrude "Extrude1" add sketch "Sketch1" along normal blind 4 makes body 1 at (3.4956, 12.3255, 2.6667) makes body 2 at (3.4956, -12.6745, 2.6667)
hole "Hole1" at (0, 12.5, 4) direction (0, 0, -1) diameter 5 end through all counterbore diameter 5.5 counterbore depth 1.5 bodies 1
hole "Hole2" at (0, -12.5, 4) direction (0, 0, -1) diameter 5 end through all counterbore diameter 5.5 counterbore depth 1.5 bodies 2
equation "d4 = ( 25 / 2 ) * 1 mm"
